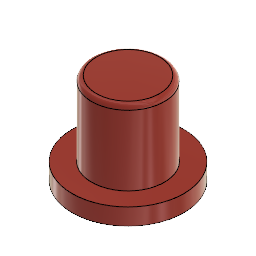
Axle_8 (Autodesk Fusion 360 design; units mm, degrees)
Autodesk Fusion 360 part; units mm, degrees
sketch "Sketch1" plane through (0, 0, 0) normal (0, 0, 1) x (1, 0, 0)
  circle A0 centre (0, 0) radius 3.9
  circle A1 centre (0, 0) radius 6
  dimension "d1" = 7.8
  dimension "d2" = 12
  constraint coincident A0.centre A1.centre
  constraint concentric A0 A1
  measures "d1" diameter of A0
  measures "d2" diameter of A1
extrude "Extrude1" add sketch "Sketch1" along normal blind 8 contours A0
extrude "Extrude3" add sketch "Sketch1" against normal blind 1.8 contours A0 | A1
fillet "Fillet1" radius 0.5 1 edges at (-3.6361, -1.4103, 8)
